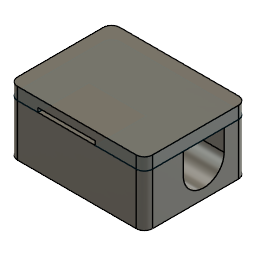
F_suporte_sensor_fluxo (Autodesk Fusion 360 design; units mm, degrees)
Autodesk Fusion 360 part; units mm, degrees
sketch "Esboço1" plane through (0, 0, 0) normal (0, 1, 0) x (1, 0, 0)
  line L0 (16.5, -12.5) -> (-16.5, -12.5)
  line L1 (-16.5, -12.5) -> (-16.5, 12.5)
  line L2 (-16.5, 12.5) -> (16.5, 12.5)
  line L3 (16.5, 12.5) -> (16.5, -12.5)
  line L4 (16.5, -12.5) -> (-16.5, 12.5) construction
  line L5 (-16.5, -12.5) -> (16.5, 12.5) construction
  dimension "d1" = 33
  dimension "d2" = 25
  constraint horizontal L0
  constraint perpendicular L0 L1
  constraint parallel L0 L2
  constraint parallel L1 L3
  constraint coincident L4 origin
  constraint coincident L5 origin
  measures "d1" distance of L1.end L2.end
  measures "d2" distance of L0.end L1.end
extrude "Extrusão1" add sketch "Esboço1" along normal blind 8.6 makes body 1
sketch "Esboço2" plane through (0, 8.6, 0) normal (0, 1, 0) x (-1, 0, 0)
  line L0 (-16.5, -12.5) -> (16.5, -12.5)
  line L1 (16.5, -12.5) -> (16.5, 12.5)
  line L2 (16.5, 12.5) -> (-16.5, 12.5)
  line L3 (-16.5, 12.5) -> (-16.5, -12.5)
  line L4 (-11.5, 8) -> (11.5, 8)
  line L5 (11.5, 8) -> (11.5, -8)
  line L6 (11.5, -8) -> (-11.5, -8)
  line L7 (-11.5, -8) -> (-11.5, 8)
  line L8 (-11.5, 8) -> (11.5, -8) construction
  line L9 (11.5, 8) -> (-11.5, -8) construction
  dimension "d5" = 23
  dimension "d6" = 16
  constraint horizontal L4
  constraint perpendicular L4 L5
  constraint parallel L4 L6
  constraint parallel L5 L7
  constraint coincident L8 origin
  constraint coincident L9 origin
  measures "d5" distance of L5.end L6.end
  measures "d6" distance of L4.end L5.end
extrude "Extrusão2" cut sketch "Esboço2" against normal blind 3.5 contours L4 L5 L6 L7 bodies 1
sketch "Esboço3" plane through (16.5, 0, 0) normal (1, 0, 0) x (0, 0, -1)
  line L0 (-12.5, 0) -> (12.5, 0)
  line L1 (12.5, 0) -> (12.5, 8.6)
  line L2 (12.5, 8.6) -> (-12.5, 8.6)
  line L3 (-12.5, 8.6) -> (-12.5, 0)
  line L4 (-8.0102, 8.6) -> (1.9898, 8.6)
  line L5 (-0.5102, 3.4) -> (4.4898, 3.4)
  line L6 (4.4898, 3.4) -> (4.4898, 8.6)
  line L7 (4.4898, 8.6) -> (-0.5102, 8.6)
  line L8 (-0.5102, 8.6) -> (-0.5102, 3.4)
  arc A0 (-0.5102, 3.4) -> (4.4898, 3.4) centre (1.9898, 3.4) ccw
  line L9 (1.9898, 8.6) -> (1.9898, 3.4)
  dimension "d9" = 10
  dimension "d10" = 5.2
  dimension "d11" = 5
  dimension "d19" = 5
  constraint coincident L2 L4.start
  constraint horizontal L5
  constraint vertical L6
  constraint horizontal L7
  constraint vertical L8
  constraint coincident L2 L6.end
  constraint coincident A0.centre L9.end
  constraint perpendicular L5 L9
  measures "d9" distance of L4.start L4.end
  measures "d10" distance of L4.end A0.centre
  measures "d11" diameter of A0
  measures "d19" distance of L5.start L5.end
extrude "Extrusão3" cut sketch "Esboço3" against normal blind 33 contours L2 L5 L6 L7 L9 | L2 L4 L5 L7 L8 L9 | L5 A0 bodies 1
sketch "Esboço5" plane through (0, 8.6, 0) normal (0, 1, 0) x (-1, 0, 0)
  circle A0 centre (13.9231, -10.0087) radius 2
  line L0 (0, 0) -> (0, -11.9776)
  line L1 (0, 0) -> (19.3611, 0)
  circle A1 centre (-13.9231, -10.0087) radius 2
  circle A2 centre (13.9231, 10.0087) radius 2
  circle A3 centre (-13.9231, 10.0087) radius 2
  circle A4 centre (13.9231, 10.0087) radius 1.85
  circle A5 centre (-13.9231, 10.0087) radius 1.85
  circle A6 centre (13.9231, -10.0087) radius 1.85
  circle A7 centre (-13.9231, -10.0087) radius 1.85
  dimension "d14" = 4
  dimension "d42" = 3.7
  dimension "d43" = 3.7
  dimension "d44" = 3.7
  dimension "d45" = 3.7
  constraint coincident L0.start L1.start
  constraint vertical L0
  constraint perpendicular L0 L1
  constraint symmetric A0 L0 A1
  constraint symmetric A0 L1 A2
  constraint symmetric L1 A1 A3
  constraint concentric A2 A4
  constraint concentric A3 A5
  constraint concentric A0 A6
  constraint concentric A1 A7
  measures "d14" diameter of A0
  measures "d42" diameter of A4
  measures "d43" diameter of A5
  measures "d44" diameter of A6
  measures "d45" diameter of A7
extrude "Extrusão4" cut sketch "Esboço5" against normal blind 5 contours A0 | A1 | A2 | A3 | A4 | A5 | A6 | A7 bodies 1
fillet "Arredondamento1" radius 2 4 edges at (-16.5, 4.3, 12.5) (-16.5, 4.3, -12.5) (16.5, 4.3, 12.5) (16.5, 4.3, -12.5) on bodies 1
sketch "Esboço6" plane through (16.5, 0, 0) normal (1, 0, 0) x (0, 0, -1)
  line L0 (10.5, 0) -> (10.5, 8.6)
  line L1 (10.5, 8.6) -> (4.4898, 8.6)
  line L2 (4.4898, 8.6) -> (4.4898, 3.4)
  arc A0 (-0.5102, 3.4) -> (4.4898, 3.4) centre (1.9898, 3.4) ccw
  line L3 (-0.5102, 3.4) -> (-0.5102, 8.6)
  line L4 (-0.5102, 8.6) -> (-10.5, 8.6)
  line L5 (-10.5, 8.6) -> (-10.5, 0)
  line L6 (-10.5, 0) -> (10.5, 0)
  line L7 (4.9898, 8.6) -> (-1.0102, 8.6)
  arc A1 (-3.0008, 3.7054) -> (6.9898, 3.4) centre (1.9898, 3.4) ccw
  line L8 (-3.0008, 3.7054) -> (-3.0008, 8.6)
  line L9 (6.9898, 3.4) -> (6.9898, 8.6)
  dimension "d20" = 10
  dimension "d26" = 6
  constraint concentric A0 A1
  constraint horizontal L7
  constraint coincident L4 L8.end
  constraint perpendicular L4 L8
  constraint coincident L1 L9.end
  constraint tangent A1 L9
  constraint perpendicular L1 L9
  measures "d20" diameter of A1
  measures "d26" distance of L7.start L7.end
extrude "Extrusão6" add 1 faces at (-4.8333, 0, 4.1667) along direction (0, -1, 0) blind 4 on bodies 1 bodies 1
extrude "Extrusão5" cut sketch "Esboço6" against normal blind 33 contours L6 A1 | L1 L2 A0 L3 L4 L6 L7 A1 L8 L9 | L2 A0 L3 L7 bodies 1
ref_plane "Plano de trabalho1" through (0, 11.6, 0) normal (0, 1, 0) x (-1, 0, 0)
sketch "Esboço8" plane through (0, 11.6, 0) normal (0, 1, 0) x (1, 0, 0)
  line L0 (14.5, -12.5) -> (-14.5, -12.5)
  line L1 (-16.5, -10.5) -> (-16.5, 10.5)
  line L2 (-14.5, 12.5) -> (14.5, 12.5)
  line L3 (16.5, 10.5) -> (16.5, -10.5)
  line L4 (16.5, -12.5) -> (-16.5, 12.5) construction
  line L5 (-16.5, -12.5) -> (16.5, 12.5) construction
  arc A0 (-14.5, 12.5) -> (-16.5, 10.5) centre (-14.5, 10.5) ccw
  arc A1 (16.5, 10.5) -> (14.5, 12.5) centre (14.5, 10.5) ccw
  arc A2 (14.5, -12.5) -> (16.5, -10.5) centre (14.5, -10.5) ccw
  arc A3 (-16.5, -10.5) -> (-14.5, -12.5) centre (-14.5, -10.5) ccw
  dimension "d28" = 33
  dimension "d29" = 25
  dimension "d30" = 2
  dimension "d31" = 2
  constraint horizontal L0
  constraint perpendicular L0 L1
  constraint parallel L0 L2
  constraint parallel L1 L3
  constraint coincident L4 origin
  constraint coincident L5 origin
  constraint coincident L4.end L2
  constraint coincident L4.end L1
  constraint tangent L2 A0
  constraint tangent L1 A0
  constraint coincident L5.end L2
  constraint coincident L5.end L3
  constraint tangent L2 A1
  constraint tangent L3 A1
  constraint coincident L4.start L3
  constraint coincident L4.start L0
  constraint tangent L3 A2
  constraint tangent L0 A2
  constraint equal A1 A2
  constraint coincident L5.start L0
  constraint coincident L5.start L1
  constraint tangent L0 A3
  constraint tangent L1 A3
  constraint equal A1 A3
  measures "d28" distance of L4.end L5.end
  measures "d29" distance of L5.start L4.end
  measures "d30" radius of A0
  measures "d31" radius of A1
extrude "Extrusão7" add sketch "Esboço8" against normal blind 3 separate body makes body 2
copy_body "Corpo -> Componente1" bodies 1 removing the originals makes body 3 in component "Component"
copy_body "Corpo -> Componente2" bodies 2 removing the originals makes body 4 in component "Component'"
sketch "Esboço10" plane through (0, 8.6, 0) normal (0, 1, 0) x (-1, 0, 0)
  line L0 (11.5, 8) -> (9.5, 8)
  line L1 (9.5, 8) -> (-4.5, 8)
  line L2 (-4.5, 8) -> (-4.5, 0)
  line L3 (-4.5, 0) -> (9.5, 0)
  line L4 (9.5, 0) -> (9.5, 8)
  line L5 (9.5, 8) -> (-4.5, 8)
  line L6 (-4.5, 8) -> (-4.5, 13)
  line L7 (-4.5, 13) -> (9.5, 13)
  line L8 (9.5, 13) -> (9.5, 8)
  point P0 (11.5, 8)
  dimension "d36" = 2
  dimension "d37" = 14
  dimension "d38" = 8
  dimension "d41" = 5
  constraint coincident P0 L0.start
  constraint horizontal L1
  constraint vertical L2
  constraint horizontal L3
  constraint vertical L4
  constraint horizontal L5
  constraint vertical L6
  constraint horizontal L7
  constraint vertical L8
  measures "d36" distance of P0 L0.end
  measures "d37" distance of L0.end L1.end
  measures "d38" distance of L0.end L3.end
  measures "d41" distance of L0.end L7.end
extrude "Extrusão2'" cut sketch "Esboço10" along normal blind 1 bodies 4 in component "Component'"
sketch "Esboço11" plane through (0, 8.6, 0) normal (0, -1, 0) x (1, 0, 0)
  line L0 (-9.5, 0) -> (-9.5, 12.5)
  line L1 (-9.5, 12.5) -> (-14.5, 12.5)
  arc A0 (-14.5, 12.5) -> (-16.5, 10.5) centre (-14.5, 10.5) ccw
  line L2 (-16.5, 10.5) -> (-16.5, -10.5)
  arc A1 (-16.5, -10.5) -> (-14.5, -12.5) centre (-14.5, -10.5) ccw
  line L3 (-14.5, -12.5) -> (14.5, -12.5)
  arc A2 (14.5, -12.5) -> (16.5, -10.5) centre (14.5, -10.5) ccw
  line L4 (16.5, -10.5) -> (16.5, 10.5)
  arc A3 (16.5, 10.5) -> (14.5, 12.5) centre (14.5, 10.5) ccw
  line L5 (14.5, 12.5) -> (4.5, 12.5)
  line L6 (4.5, 12.5) -> (4.5, 0)
  line L7 (4.5, 0) -> (-9.5, 0)
extrude "Extrusão3'" add sketch "Esboço5" against normal blind 4.8 contours A4 | A5 | A6 | A7 bodies 4 in component "Component'"
component "Component" placed x (1, 0, 0) y (0, 1, 0) z (0, 0, 1) at (0, 0, 0)
component "Component'" placed x (1, 0, 0) y (0, 1, 0) z (0, 0, 1) at (0, 0, 0)
